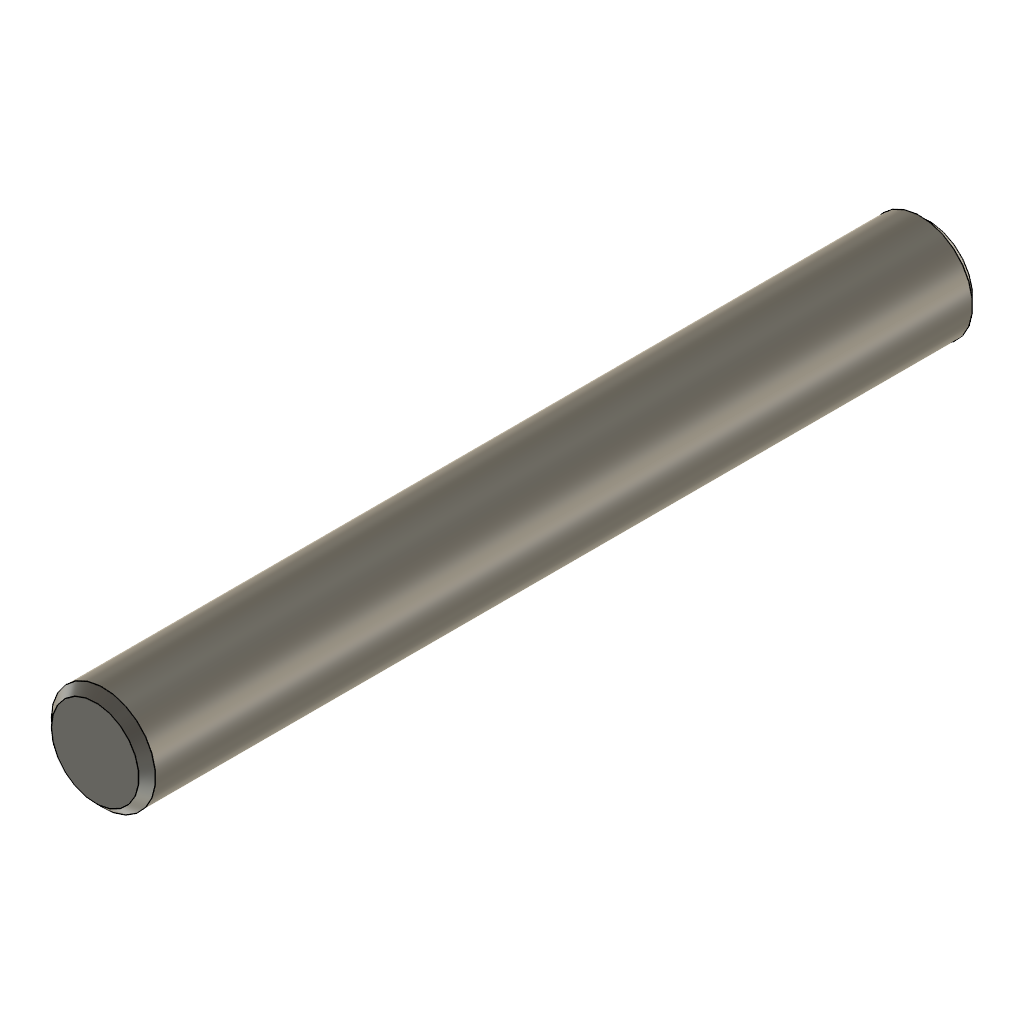
Pin_for_pinion (Autodesk Fusion 360 design; units mm, degrees)
part number: 2026-10-29-00-36-52-062
Autodesk Fusion 360 part; units mm, degrees
sketch "Sketch1" plane through (0, 0, 0) normal (0, 1, 0) x (1, 0, 0)
  circle A0 centre (0, 0) radius 1.5875
  dimension "d1" = 3.175
  constraint coincident A0.centre origin
  measures "d1" diameter of A0
extrude "Extrude1" add sketch "Sketch1" along normal blind 25.4
chamfer "Chamfer1" distance 0.254 angle 45 1 edges at (-1.4801, 0, 0.5741) tangent chain off
chamfer "Chamfer2" distance 0.254 angle 45 1 edges at (-1.4801, 25.4, 0.5741) tangent chain off
